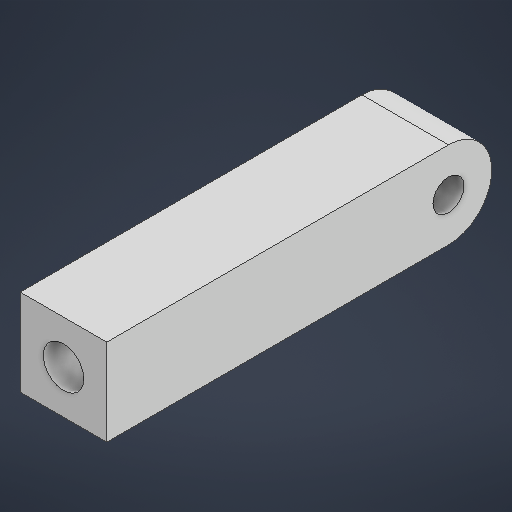
# Autodesk Inventor part: Lower leg to lower G connector_8
Saved by Autodesk Inventor 2027 (Build 310192060, 192F)
## iProperties
Created: 2026-06-30
Part Number: Lower leg to lower G connector_8
Material: Generic
Document SubType Name: Modeling
Designer: troop
Density: 1 g/cm^3
Appearance: Default
Author: troop
Autodesk Inventor part; units mm, degrees
ref_plane "YZ Plane" through (0, 0, 0) normal (1, 0, 0) x (0, 1, 0)
ref_plane "XZ Plane" through (0, 0, 0) normal (0, 1, 0) x (-1, 0, 0)
ref_plane "XY Plane" through (0, 0, 0) normal (0, 0, 1) x (1, 0, 0)
sketch "Sketch1" plane through (0, 0, 0) normal (0, 0, 1) x (1, 0, 0)
  line L0 (0, 0) -> (11.43, 0)
  line L1 (11.43, 0) -> (11.43, 11.43)
  line L2 (11.43, 11.43) -> (0, 11.43)
  line L3 (0, 11.43) -> (0, 0)
  circle A0 centre (5.715, 5.715) radius 2.675
  point P0 (5.715, 0)
  dimension "d1" = 11.43
  dimension "d2" = 11.43
  dimension "d9" = 5.35
  dimension "d10" = 5.715
  dimension "d11" = 5.715
  constraints: 8 end point, 2 parallel, 1 centre point, 1 horizontal, 1 midpoint, 1 perpendicular
  measures "d1" distance of L1.end L2.end
  measures "d2" distance of L0.end L1.end
  measures "d9" diameter of A0
  measures "d10" distance from line of L3 A0.centre
  measures "d11" distance of point (5.715, 0) A0.centre
extrude "Extrusion1" add sketch "Sketch1" against normal blind 50.8 contours L3 L2 L1 L0 | A0
extrude "Extrusion3" cut sketch "Sketch1" against normal blind 25.4 contours A0
fillet "Fillet1" radius 5.715 1 edges at (5.715, 11.43, -50.8)
fillet "Fillet2" radius 5.715 1 edges at (5.715, 0, -50.8)
sketch "Sketch2" plane through (11.43, 0, 0) normal (1, 0, 0) x (0, 0, -1)
  circle A0 centre (45.085, 5.715) radius 2.05
  line L0 (0, 0) -> (50.8, 0) projected
  arc A1 (50.8, 5.715) -> (45.085, 11.43) centre (45.085, 5.715) ccw projected
  point P0 (45.085, 0)
  dimension "d16" = 4.1
  dimension "d17" = 5.715
  dimension "d18" = 5.715
  constraints: 1 centre point, 1 point on circle
  measures "d16" diameter of A0
  measures "d17" distance from line of L0 A0.centre
  measures "d18" distance of A1.start A0.centre
extrude "Extrusion4" cut sketch "Sketch2" against normal blind 25.4
body "Solid1"
